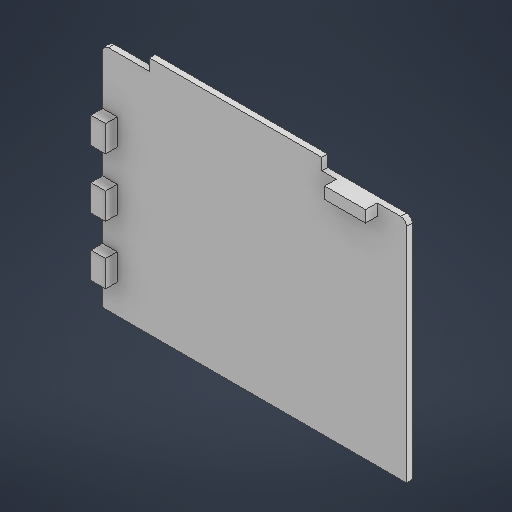
# Autodesk Inventor part: 显示屏电路板
Saved by Autodesk Inventor 2025 (Build 290162000, 162)
## iProperties
Created: 2025-09-26
Part Number: 显示屏电路板
Material: 常规
Document SubType Name: Modeling
Designer: HZD
Density: 1 g/cm^3
Appearance: 默认
Author: HZD
Autodesk Inventor part; units mm, degrees
ref_plane "YZ Plane" through (0, 0, 0) normal (1, 0, 0) x (0, 1, 0)
ref_plane "XZ Plane" through (0, 0, 0) normal (0, 1, 0) x (-1, 0, 0)
ref_plane "XY Plane" through (0, 0, 0) normal (0, 0, 1) x (1, 0, 0)
sketch "草图1" plane through (0, 0, 0) normal (0, 0, 1) x (1, 0, 0)
  line L0 (26, -20.5) -> (-26, -20.5)
  line L1 (-26, -20.5) -> (-26, 20.5)
  line L2 (-26, 20.5) -> (26, 20.5)
  line L3 (26, 20.5) -> (26, -20.5)
  line L4 (26, -20.5) -> (-26, 20.5) construction
  line L5 (-26, -20.5) -> (26, 20.5) construction
  point P0 (0, 0)
  dimension "d0" = 52
  dimension "d1" = 41
  constraints: 12 end point, 2 midpoint, 2 parallel, 1 horizontal, 1 perpendicular
  measures "d0" distance of L1.end L2.end
  measures "d1" distance of L2.end L0.start
extrude "拉伸1" add sketch "草图1" along normal blind 1
sketch "草图2" plane through (0, 0, 1) normal (0, 0, 1) x (1, 0, 0)
  line L0 (26, 20.5) -> (-26, 20.5) projected
  line L1 (-26, 20.5) -> (-18, 20.5)
  line L2 (-18, 20.5) -> (-18, 18.5)
  line L3 (-18, 18.5) -> (-26, 18.5)
  line L4 (-26, 18.5) -> (-26, 20.5)
  line L5 (11.5, 20.5) -> (26, 20.5)
  line L6 (26, 20.5) -> (26, 18.5)
  line L7 (26, 18.5) -> (11.5, 18.5)
  line L8 (11.5, 18.5) -> (11.5, 20.5)
  line L9 (26, -20.5) -> (26, 20.5) projected
  point P0 (0, 0)
  point P1 (-26, 19.5)
  point P2 (-18, 19.5)
  point P3 (11.5, 19.5)
  point P4 (26, 19.5)
  dimension "d4" = 2
  dimension "d5" = 8
  dimension "d6" = 2
  dimension "d7" = 14.5
  constraints: 16 end point, 4 midpoint, 4 parallel, 2 horizontal, 2 perpendicular, 1 collinear, 1 point on line
  measures "d4" distance between parallel lines of L3 L0
  measures "d5" distance of point (-26, 19.5) point (-18, 19.5)
  measures "d6" distance between parallel lines of L0 L7
  measures "d7" distance of point (11.5, 19.5) point (26, 19.5)
extrude "拉伸2" cut sketch "草图2" against normal blind 1
fillet "圆角1" radius 1 2 edges at (26, 18.5, 0.5) (-26, 18.5, 0.5)
sketch "草图3" plane through (0, 0, 1) normal (0, 0, 1) x (1, 0, 0)
  line L0 (14, 18.5) -> (21, 18.5)
  line L1 (21, 18.5) -> (21, 16.5)
  line L2 (21, 16.5) -> (14, 16.5)
  line L3 (14, 16.5) -> (14, 18.5)
  line L4 (26, -20.5) -> (26, 17.5) projected
  line L5 (25, 18.5) -> (11.5, 18.5) projected
  point P0 (0, 0)
  point P1 (21, 17.5)
  dimension "d11" = 5
  dimension "d12" = 2
  dimension "d13" = 7
  constraints: 8 end point, 2 parallel, 1 collinear, 1 horizontal, 1 midpoint, 1 perpendicular
  measures "d11" distance from line of point (21, 17.5) L4
  measures "d12" distance between parallel lines of L0 L2
  measures "d13" distance from line of L3 L1.end
extrude "拉伸3" add sketch "草图3" along normal blind 2
sketch "草图4" plane through (0, 0, 1) normal (0, 0, 1) x (1, 0, 0)
  line L0 (-26, -15.5) -> (-23.5, -15.5)
  line L1 (-23.5, -15.5) -> (-23.5, -11)
  line L2 (-23.5, -11) -> (-26, -11)
  line L3 (-26, -11) -> (-26, -15.5)
  line L4 (-26, -20.5) -> (26, -20.5) projected
  line L5 (-26, 17.5) -> (-26, -20.5) projected
  line L6 (-26, -5.5) -> (-23.5, -5.5)
  line L7 (-23.5, -5.5) -> (-23.5, -1)
  line L8 (-23.5, -1) -> (-26, -1)
  line L9 (-26, -1) -> (-26, -5.5)
  line L10 (-26, 4.5) -> (-23.5, 4.5)
  line L11 (-23.5, 4.5) -> (-23.5, 9)
  line L12 (-23.5, 9) -> (-26, 9)
  line L13 (-26, 9) -> (-26, 4.5)
  point P0 (0, 0)
  point P1 (-24.75, -15.5)
  point P2 (-23.5, -13.25)
  point P3 (-26, -13.25)
  point P4 (-24.75, -1)
  point P5 (-24.75, -11)
  point P6 (-24.75, -5.5)
  point P7 (-24.75, 9)
  point P8 (-24.75, 4.5)
  dimension "d16" = 5
  dimension "d17" = 2.5
  dimension "d18" = 4.5
  dimension "d19" = 4.5
  dimension "d20" = 5.5
  dimension "d21" = 4.5
  dimension "d22" = 5.5
  constraints: 24 end point, 8 midpoint, 6 parallel, 3 collinear, 3 horizontal, 3 perpendicular, 2 point on line
  measures "d16" distance from line of L4 point (-24.75, -15.5)
  measures "d17" distance of point (-23.5, -13.25) point (-26, -13.25)
  measures "d18" distance between parallel lines of L2 L0
  measures "d19" distance from line of L6 point (-24.75, -1)
  measures "d20" distance of point (-24.75, -11) point (-24.75, -5.5)
  measures "d21" distance of point (-24.75, 9) point (-24.75, 4.5)
  measures "d22" distance between parallel lines of L8 L10
extrude "拉伸4" add sketch "草图4" along normal blind 2
sketch "草图5" plane through (0, 0, 0) normal (0, 0, -1) x (-1, 0, 0)
  line L0 (15.9068, -11.1489) -> (-5.965, -11.1489)
  line L1 (-5.965, -11.1489) -> (-5.965, -5.539)
  line L2 (-5.965, -5.539) -> (15.9068, -5.539)
  line L3 (15.9068, -5.539) -> (15.9068, -11.1489)
  point P0 (0, 0)
  constraints: 8 end point, 2 parallel, 1 horizontal, 1 perpendicular
extrude "拉伸5" add sketch "草图5" along normal blind 1.5
